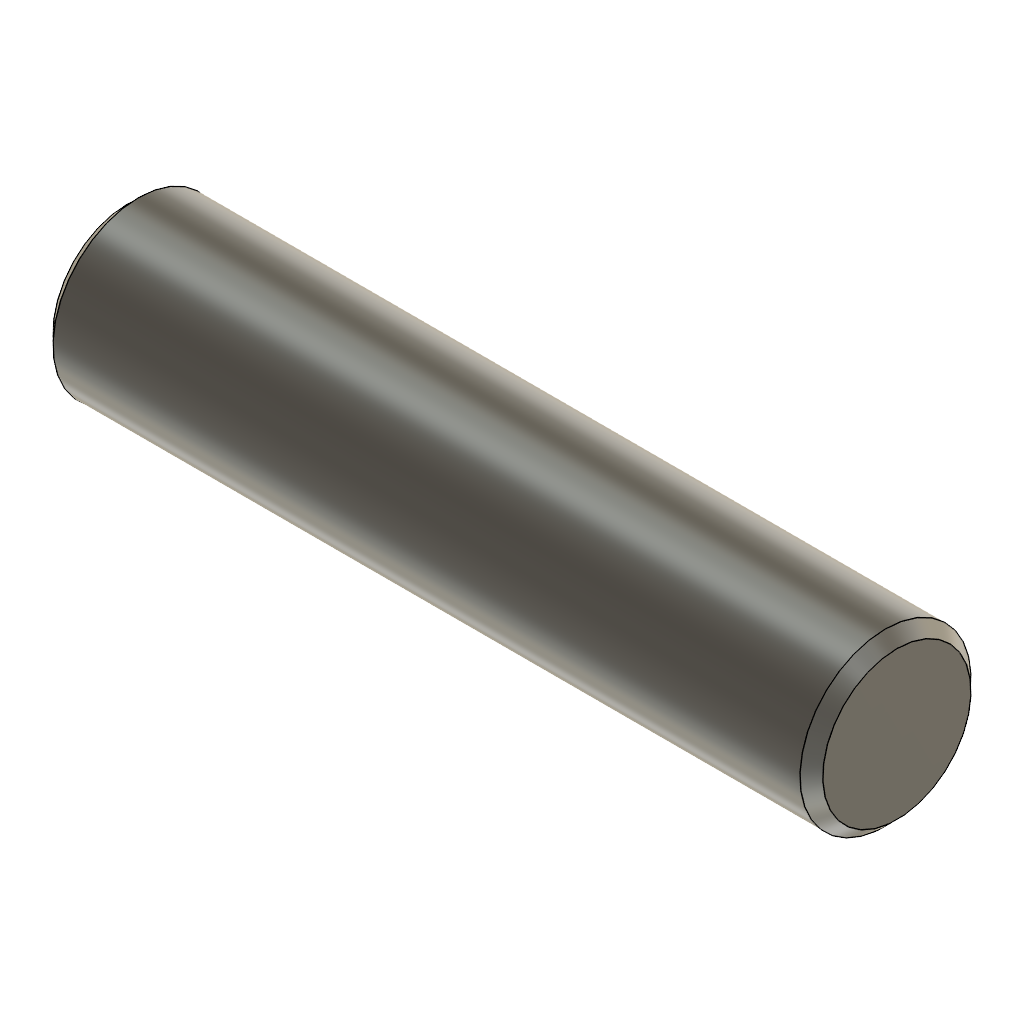
source (Autodesk Fusion 360 archive; units mm, degrees)
design "11_piston_pin"
Autodesk Fusion 360 part; units mm, degrees
sketch "Sketch1" plane through (0, 0, 0) normal (0, 1, 0) x (1, 0, 0)
  line L0 (-6.75, 0) -> (6.75, 0)
  line L1 (6.75, 0) -> (6.75, -1.3)
  line L2 (6.55, -1.5) -> (-6.55, -1.5)
  line L3 (-6.75, 0) -> (-6.75, -1.3)
  line L4 (6.75, -1.3) -> (6.55, -1.5)
  line L5 (-6.55, -1.5) -> (-6.75, -1.3)
  point P0 (6.75, -1.5)
  point P1 (-6.75, -1.5)
  dimension "d1" = 13.5
  dimension "d2" = 1.5
  dimension "d3" = 0.2
  dimension "d4" = 0.2
  dimension "d5" = 0.2
  dimension "d6" = 0.2
  constraint midpoint L0 origin
  constraint horizontal L0
  constraint vertical L1
  constraint perpendicular L1 L2
  constraint perpendicular L2 L3
  constraint coincident P0 L1
  constraint coincident P0 L2
  constraint coincident P1 L2
  constraint coincident P1 L3
  measures "d1" distance of L0.start L0.end
  measures "d2" distance of L0.end P0
  measures "d3" distance of P0 L1.end
  measures "d4" distance of P0 L2.start
  measures "d5" distance of P1 L2.end
  measures "d6" distance of P1 L3.end
revolve "Revolve1" add sketch "Sketch1" angle 360 about axis through (-6.75, 0, 0) along (1, 0, 0)
equation "d4 = d3"
equation "d6 = d5"

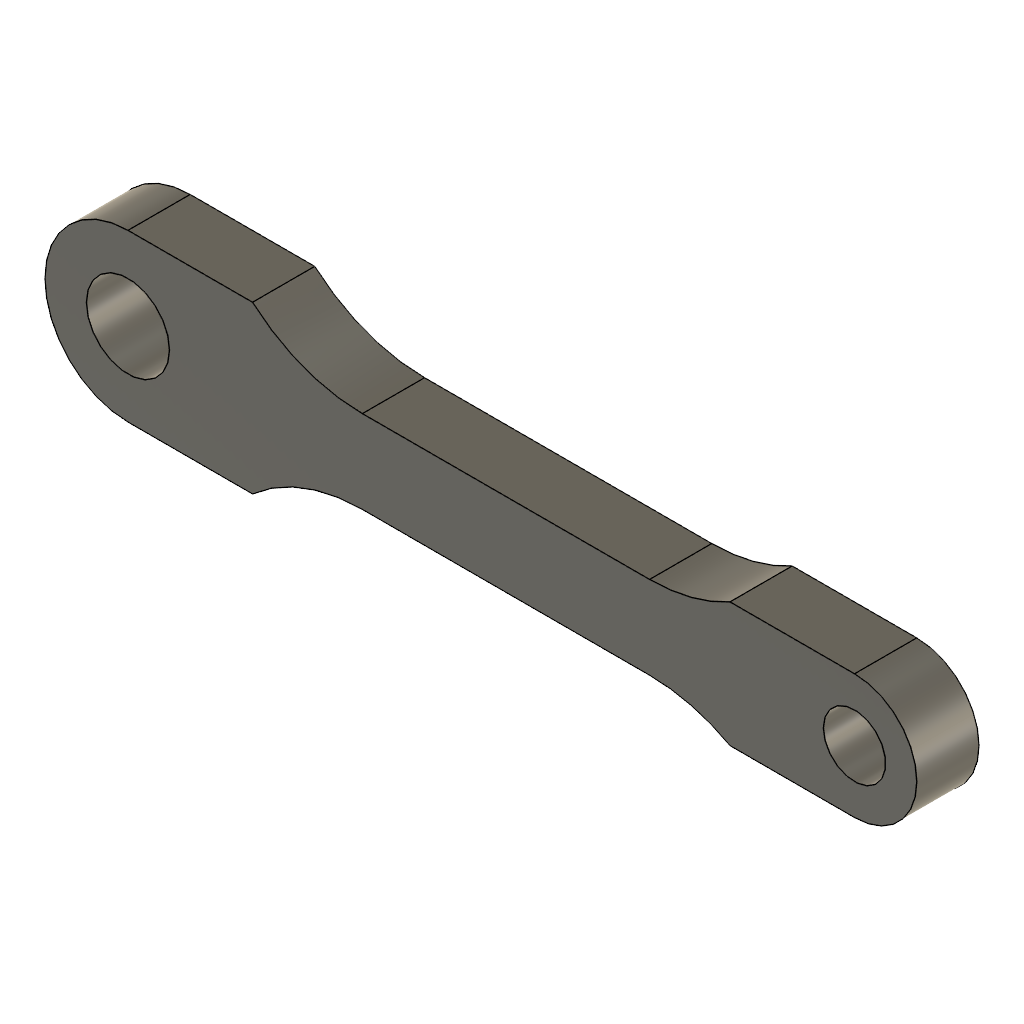
design "08_connecting_rod"
Autodesk Fusion 360 part; units mm, degrees
sketch "Sketch1" plane through (0, 0, 0) normal (0, 1, 0) x (1, 0, 0)
  line L0 (-17.5, 0) -> (17.5, 0) construction
  circle A0 centre (-17.5, 0) radius 2
  circle A1 centre (17.5, 0) radius 1.5
  arc A2 (-17.5, 4) -> (-17.5, -4) centre (-17.5, 0) ccw
  arc A3 (17.5, -3) -> (17.5, 3) centre (17.5, 0) ccw
  line L1 (17.5, 3) -> (11.5, 3)
  arc A4 (7.627, 2) -> (11.5, 3) centre (7.627, 10) ccw
  line L2 (7.627, 2) -> (-6.2085, 2)
  arc A5 (-11.5, 4) -> (-6.2085, 2) centre (-6.2085, 10) ccw
  line L3 (-17.5, 4) -> (-11.5, 4)
  arc A6 (-17.5, 4) -> (-17.5, -4) centre (-17.5, 0) ccw
  line L4 (7.627, -2) -> (-6.2085, -2)
  arc A7 (11.5, -3) -> (7.627, -2) centre (7.627, -10) ccw
  line L5 (17.5, -3) -> (11.5, -3)
  arc A8 (17.5, -3) -> (17.5, 3) centre (17.5, 0) ccw
  line L6 (-17.5, -4) -> (-11.5, -4)
  arc A9 (-6.2085, -2) -> (-11.5, -4) centre (-6.2085, -10) ccw
  dimension "d1" = 35
  dimension "d2" = 4
  dimension "d3" = 3
  dimension "d4" = 4
  dimension "d5" = 3
  dimension "d6" = 6
  dimension "d7" = 6
  dimension "d8" = 8
  dimension "d9" = 2
  constraint midpoint L0 origin
  constraint horizontal L0
  constraint coincident L0.start A0.centre
  constraint coincident L0.end A1.centre
  constraint horizontal L1
  constraint horizontal L2
  constraint tangent L2 A5
  constraint tangent A2 L3
  constraint horizontal L3
  constraint equal A4 A5
  constraint tangent A4 L2
  constraint tangent A3 L1
  constraint vertical L0.start A2.end
  constraint vertical L0.end A3.start
  constraint symmetric L0 A2.start A2.end
  constraint symmetric L0 A2.end A2.start
  constraint symmetric L0 A2 A6
  constraint symmetric L0 A3.start A3.end
  constraint symmetric L0 A3.end A3.start
  constraint symmetric L0 A3 A8
  constraint symmetric L0 L1.end A7.start
  constraint symmetric L0 A4.start L4.start
  constraint symmetric L0 A4 A7
  constraint symmetric L0 L2.end L4.end
  constraint symmetric L0 A5 A9
  constraint symmetric L0 A5.start L6.end
  measures "d1" distance of L0.start L0.end
  measures "d2" diameter of A0
  measures "d3" diameter of A1
  measures "d4" radius of A2
  measures "d5" radius of A3
  measures "d6" distance of A3.end L1.end
  measures "d7" distance of A2.start A5.start
  measures "d8" radius of A5
  measures "d9" distance of L0 L2
extrude "Extrude1" add sketch "Sketch1" along normal mid plane 3

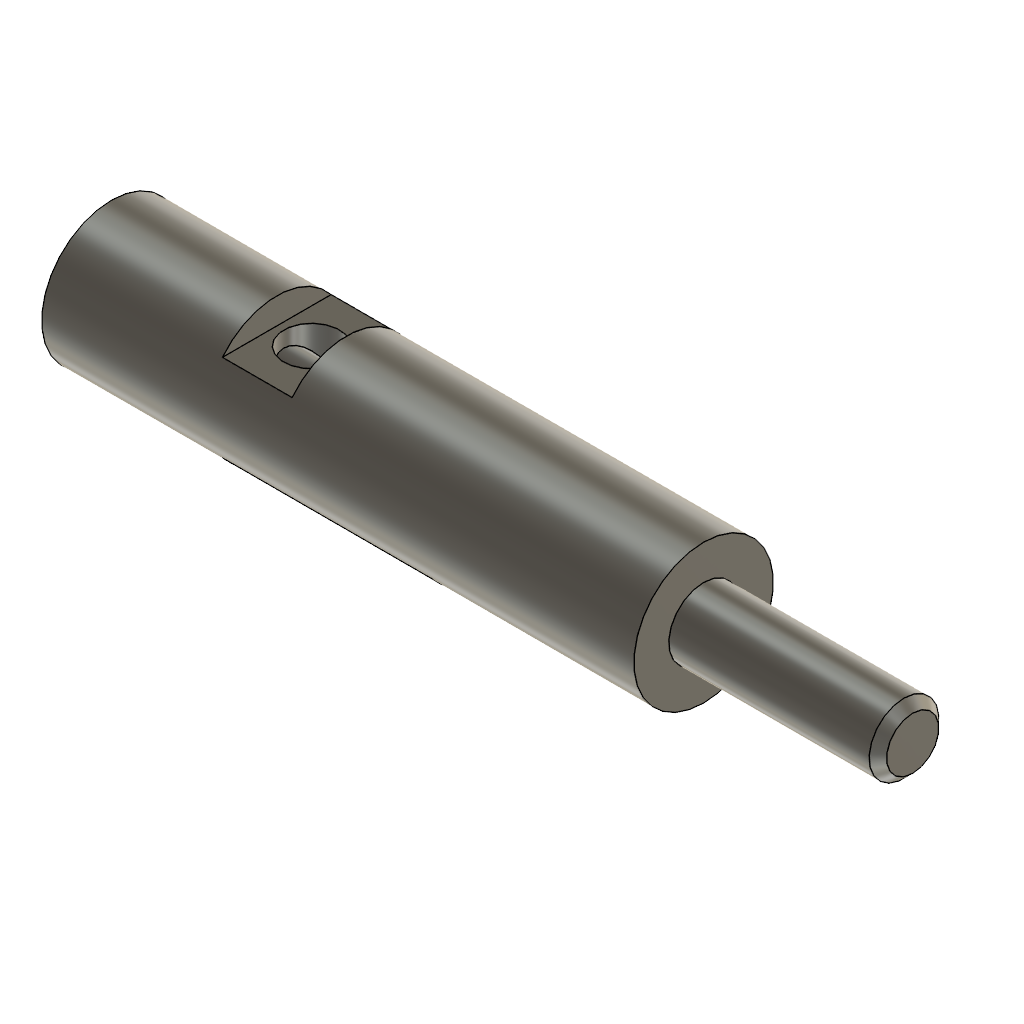
design "06_cranckshaft"
Autodesk Fusion 360 part; units mm, degrees
sketch "Sketch1" plane through (0, 0, 0) normal (0, 1, 0) x (1, 0, 0)
  line L0 (-23, 0) -> (23, 0)
  line L1 (-23, 0) -> (-23, -4)
  line L2 (-23, -4) -> (11, -4)
  line L3 (11, -4) -> (11, -2)
  line L4 (11, -2) -> (22.5, -2)
  line L5 (23, -1.5) -> (23, 0)
  line L6 (-23, 0) -> (-23, -1.6)
  line L7 (-23, -1.6) -> (-9, -1.6)
  line L8 (-9, -1.6) -> (-8.0762, 0)
  line L9 (22.5, -2) -> (23, -1.5)
  point P0 (23, -2)
  dimension "d1" = 46
  dimension "d2" = 4
  dimension "d3" = 34
  dimension "d4" = 1.6
  dimension "d5" = 14
  dimension "d6" = 120
  dimension "d7" = 2
  dimension "d30" = 0.5
  dimension "d31" = 0.5
  constraint midpoint L0 origin
  constraint horizontal L0
  constraint perpendicular L0 L1
  constraint perpendicular L1 L2
  constraint perpendicular L0 L3
  constraint perpendicular L1 L4
  constraint perpendicular L0 L5
  constraint perpendicular L0 L6
  constraint perpendicular L6 L7
  constraint coincident L0 L8.end
  constraint coincident P0 L4
  constraint coincident P0 L5
  measures "d1" distance of L0.start L0.end
  measures "d2" distance of L0.start L1.end
  measures "d3" distance of L1.end L2.end
  measures "d4" distance of L0.start L6.end
  measures "d5" distance of L6.end L7.end
  measures "d6" angle of L7 L8
  measures "d7" distance of L0.end P0
  measures "d30" distance of P0 L4.end
  measures "d31" distance of P0 L5.start
revolve "Revolve1" add sketch "Sketch1" angle 360 about axis through (-23, 0, 0) along (1, 0, 0) contours L0 L1 L2 L3 L4 L5 L7 L8 L9
sketch "Sketch4" plane through (0, 0, 0) normal (0, 1, 0) x (1, 0, 0)
  line L0 (-23, 4) -> (-23, -4)
  line L1 (-23, 4) -> (-13.5, 4)
  line L2 (-13.5, 4) -> (-1.5, 4)
  line L3 (-1.5, 4) -> (-1.5, 2.5)
  line L4 (-1.5, 2.5) -> (-13.5, 2.5)
  line L5 (-13.5, 2.5) -> (-13.5, 4)
  line L6 (-23, -4) -> (-11.5, -4)
  line L7 (-9.5, -2.5) -> (-13.5, -2.5)
  line L8 (-13.5, -2.5) -> (-13.5, -5.5)
  line L9 (-13.5, -5.5) -> (-9.5, -5.5)
  line L10 (-9.5, -5.5) -> (-9.5, -2.5)
  line L11 (-9.5, -2.5) -> (-13.5, -5.5) construction
  line L12 (-13.5, -2.5) -> (-9.5, -5.5) construction
  point P0 (-11.5, -4)
  dimension "d18" = 9.5
  dimension "d19" = 12
  dimension "d20" = 1.5
  dimension "d21" = 11.5
  dimension "d22" = 4
  dimension "d23" = 3
  constraint coincident L0.start L1.start
  constraint perpendicular L0 L1
  constraint horizontal L2
  constraint vertical L3
  constraint horizontal L4
  constraint vertical L5
  constraint coincident L0.end L6.start
  constraint perpendicular L0 L6
  constraint horizontal L7
  constraint perpendicular L7 L8
  constraint parallel L7 L9
  constraint parallel L8 L10
  constraint coincident L11 P0
  constraint coincident L12 P0
  constraint coincident P0 L6.end
  measures "d18" distance of L0.start L1.end
  measures "d19" distance of L1.end L2.end
  measures "d20" distance of L1.end L4.end
  measures "d21" distance of L0.end P0
  measures "d22" distance of L8.end L9.end
  measures "d23" distance of L7.end L8.end
extrude "Extrude3" cut sketch "Sketch4" along normal mid plane 22
sketch "Sketch5" plane through (0, 0, 0) normal (0, 0, 1) x (-1, 0, 0)
  line L0 (9.5, -3.1225) -> (13.5, -3.1225)
  line L1 (13.5, -3.1225) -> (13.5, 3.1225)
  line L2 (13.5, 3.1225) -> (9.5, 3.1225)
  line L3 (9.5, 3.1225) -> (9.5, -3.1225)
  circle A0 centre (11.5, 0) radius 1.6
  point P0 (23, 0)
  dimension "d26" = 3.2
  dimension "d27" = 11.5
  measures "d26" diameter of A0
  measures "d27" distance of A0.centre P0
extrude "Extrude4" cut sketch "Sketch5" along normal blind 8 contours A0
equation "d4 = ( 3.2 / 2 ) * 1 mm"
equation "d31 = d30"

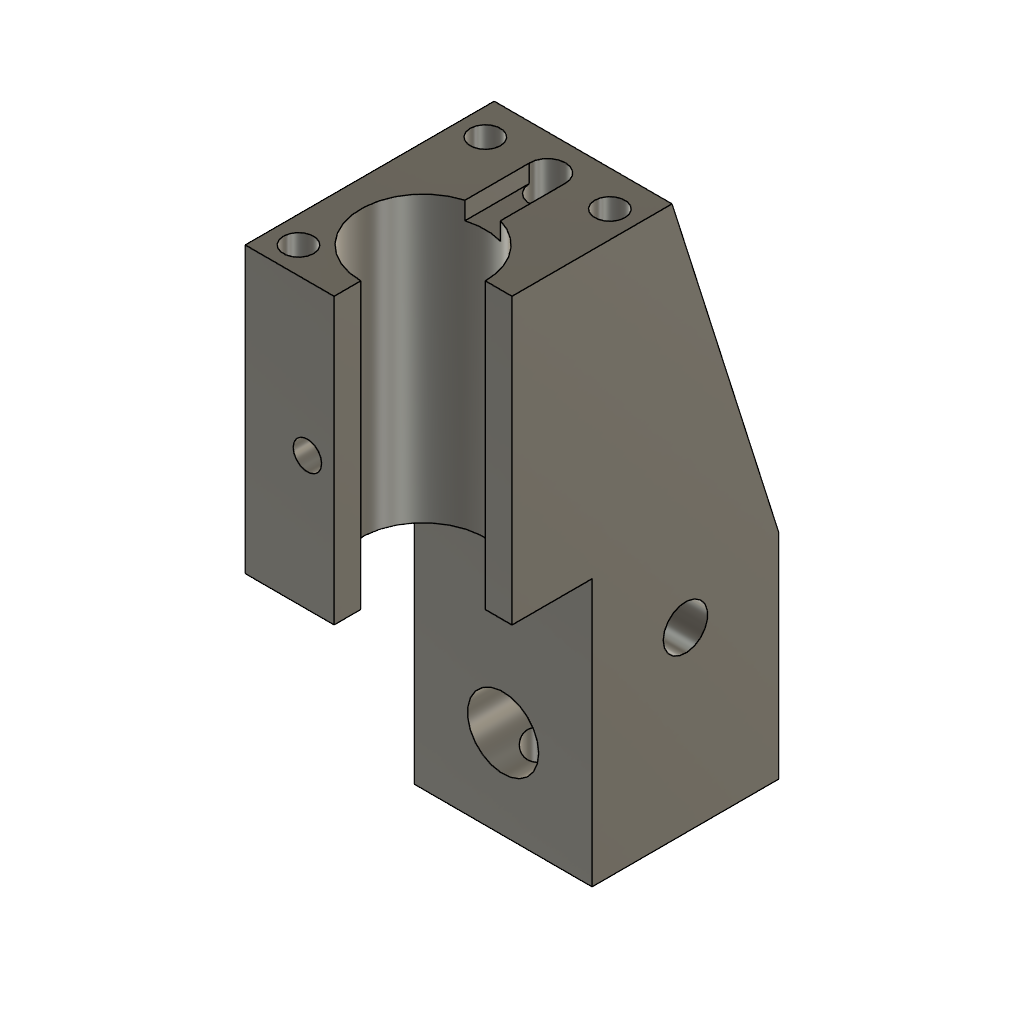
design "03_Engine_Block"
Autodesk Fusion 360 part; units mm, degrees
sketch "Sketch1" plane through (0, 0, 0) normal (1, 0, 0) x (0, 1, 0)
  line L0 (-10, 0) -> (18, 0)
  line L1 (18, 0) -> (30, -38)
  line L2 (30, -38) -> (30, -62)
  line L3 (30, -62) -> (9, -62)
  line L4 (9, -62) -> (9, -32)
  line L5 (9, -32) -> (-10, -32)
  line L6 (-10, -32) -> (-10, 0)
  circle A0 centre (19.5, -42) radius 2.5
  point P0 (19.5, -62)
  dimension "d1" = 28
  dimension "d2" = 12
  dimension "d3" = 38
  dimension "d4" = 21
  dimension "d5" = 30
  dimension "d7" = 10
  dimension "d8" = 62
  dimension "d23" = 5
  dimension "d24" = 20
  constraint horizontal L0
  constraint vertical L2
  constraint perpendicular L2 L3
  constraint perpendicular L3 L4
  constraint perpendicular L4 L5
  constraint coincident L0.start L6.end
  constraint perpendicular L5 L6
  constraint coincident origin L0
  constraint midpoint L3 P0
  constraint vertical A0.centre P0
  measures "d1" distance of L0.start L0.end
  measures "d2" horizontal distance of L0.end L1.end
  measures "d3" vertical distance of L0.end L1.end
  measures "d4" distance of L2.end L3.end
  measures "d5" vertical distance of L3.end L5.end
  measures "d7" horizontal distance of origin L0.start
  measures "d8" vertical distance of L3.end L0.start
  measures "d23" diameter of A0
  measures "d24" distance of L3 A0.centre
extrude "Extrude1" add sketch "Sketch1" along normal mid plane 20
sketch "Sketch2" plane through (0, 0, 0) normal (0, 0, 1) x (-1, 0, 0)
  line L0 (10, 10) -> (-10, 10)
  line L1 (-10, 10) -> (-10, -18)
  line L2 (-10, -18) -> (10, -18)
  line L3 (10, -18) -> (10, 10)
  circle A0 centre (0, 0) radius 7
  dimension "d11" = 14
  constraint coincident A0.centre origin
  measures "d11" diameter of A0
extrude "Extrude2" cut sketch "Sketch2" against normal blind 40 contours A0
sketch "Sketch4" plane through (0, 30, 0) normal (0, 1, 0) x (-1, 0, 0)
  line L0 (10, -38) -> (-10, -38)
  line L1 (-10, -38) -> (-10, -62)
  line L2 (-10, -62) -> (10, -62)
  line L3 (10, -62) -> (10, -38)
  circle A0 centre (0, -52) radius 4
  dimension "d20" = 8
  dimension "d21" = 10
  constraint vertical origin A0.centre
  measures "d20" diameter of A0
  measures "d21" distance of L2 A0.centre
extrude "Extrude3" cut sketch "Sketch4" against normal through all contours A0
sketch "Sketch3" plane through (0, 0, 0) normal (1, 0, 0) x (0, 1, 0)
  line L0 (18, 0) -> (-10, 0)
  line L1 (14, 0) -> (14, -49.9021)
  line L2 (14, 0) -> (12, 0)
  line L3 (12, 0) -> (12, -30)
  line L4 (12, -30) -> (12.75, -30)
  line L5 (12.75, -30) -> (12.75, -49.9021)
  line L6 (12.75, -49.9021) -> (14, -49.9021)
  dimension "d14" = 2
  dimension "d15" = 30
  dimension "d17" = 24
  dimension "d18" = 1.25
  constraint coincident L0 L1.start
  constraint perpendicular L0 L1
  constraint perpendicular L1 L2
  constraint perpendicular L0 L3
  constraint perpendicular L3 L4
  constraint vertical L5
  constraint horizontal L6
  measures "d14" distance of L1.start L2.end
  measures "d15" distance of L2.end L3.end
  measures "d17" distance of L0.end L1.start
  measures "d18" distance of L1 L5
revolve "Revolve1" cut sketch "Sketch3" angle 360 about axis through (0, 14, 0) along (0, 0, -1)
sketch "Sketch6" plane through (0, -10, 0) normal (0, -1, 0) x (1, 0, 0)
  line L0 (-10, -32) -> (10, -32)
  line L1 (10, -32) -> (10, 0)
  line L2 (10, 0) -> (-10, 0)
  line L3 (-10, 0) -> (-10, -32)
  circle A0 centre (-3, -17) radius 1.6
  circle A1 centre (3, -17) radius 1.6
  point P0 (-3, -17)
  point P1 (3, -17)
  dimension "d25" = 17
  dimension "d26" = 6
  dimension "d27" = 3
  dimension "d28" = 3.2
  constraint horizontal P0 P1
  constraint coincident P0 A0.centre
  constraint coincident P1 A1.centre
  constraint equal A0 A1
  measures "d25" vertical distance of L1.end P1
  measures "d26" distance of P0 P1
  measures "d27" horizontal distance of origin P1
  measures "d28" diameter of A0
extrude "Extrude4" cut sketch "Sketch6" against normal blind 9 contours A0 | A1
sketch "Sketch7" plane through (0, 0, 0) normal (0, 0, 1) x (-1, 0, 0)
  circle A0 centre (0, -14) radius 2
  circle A1 centre (0, 0) radius 7
  line L0 (10, 10) -> (-10, 10)
  line L1 (-10, 10) -> (-10, -18)
  line L2 (-10, -18) -> (10, -18)
  line L3 (10, -18) -> (10, 10)
  line L4 (1.9986, -14.0753) -> (-1.9986, -14.0753)
  line L5 (-1.9986, -14.0753) -> (-1.9986, -6.7086)
  line L6 (-1.9986, -6.7086) -> (1.9986, -6.7086)
  line L7 (1.9986, -6.7086) -> (1.9986, -14.0753)
  line L8 (-1.9986, -14.0753) -> (1.9986, -14.0753)
  constraint horizontal L4
  constraint vertical L5
  constraint horizontal L6
  constraint vertical L7
  constraint coincident A1 L5.end
  constraint coincident A0 L4.start
  constraint coincident A0 L4.end
  constraint perpendicular L7 L8
extrude "Extrude5" cut sketch "Sketch7" against normal blind 2 contours A0 L4 L5 L7 L8 | A0 A1 L5 L7 | A1 L6 picked at (-0.3366, -6.7813)
sketch "Sketch8" plane through (0, 0, 0) normal (0, 0, 1) x (-1, 0, 0)
  line L0 (10, 10) -> (-10, 10)
  line L1 (-10, 10) -> (-10, -18)
  line L2 (-10, -18) -> (10, -18)
  line L3 (10, -18) -> (10, 10)
  line L4 (1.9986, -6.7086) -> (1.9986, -13.9247)
  arc A0 (-1.9986, -13.9247) -> (1.9986, -13.9247) centre (0, -14) ccw
  line L5 (-1.9986, -13.9247) -> (-1.9986, -6.7086)
  arc A1 (1.9986, -6.7086) -> (-1.9986, -6.7086) centre (0, 0) ccw
  point P0 (7, 7)
  point P1 (7, -14)
  point P2 (-7, -14)
  point P3 (-7, 7)
  point P4 (7, 7)
  dimension "d33" = 3
  dimension "d34" = 7
  dimension "d35" = 14
  dimension "d36" = 24
  constraint coincident P4 P0
  constraint horizontal P1 P2
  constraint vertical P2 P3
  constraint horizontal P3 P4
  constraint vertical P4 P1
  measures "d33" distance of L0 P4
  measures "d34" horizontal distance of A1.centre P4
  measures "d35" horizontal distance of P4 P3
  measures "d36" distance of L0 P1
hole "Hole1" at (-7, 14, 0) at (-7, -7, 0) at (7, -7, 0) at (7, 14, 0) direction (0, 0, -1) diameter 3.4 depth 9 tip angle 118
sketch "Sketch9" plane through (0, 0, -62) normal (0, 0, -1) x (1, 0, 0)
  line L0 (-10, -30) -> (10, -30)
  line L1 (10, -30) -> (10, -9)
  line L2 (10, -9) -> (-10, -9)
  line L3 (-10, -9) -> (-10, -30)
  point P0 (0, -22)
  point P1 (0, -14)
  point P2 (0, -30)
  dimension "d40" = 8
  dimension "d41" = 8
  constraint midpoint L0 P2
  constraint vertical P0 P2
  constraint vertical P0 P1
  measures "d40" distance of P0 P2
  measures "d41" distance of P0 P1
hole "Hole2" at (0, 22, -62) at (0, 14, -62) direction (0, 0, 1) diameter 4.5 depth 9 tip angle 118
sketch "Çizim10" plane through (0, 0, 0) normal (0, 0, 1) x (-1, 0, 0)
  line L0 (1.9986, -6.7086) -> (1.9986, -13.9247)
  arc A0 (-1.9986, -13.9247) -> (1.9986, -13.9247) centre (0, -14) ccw
  line L1 (-1.9986, -13.9247) -> (-1.9986, -6.7086)
  arc A1 (1.9986, -6.7086) -> (-1.9986, -6.7086) centre (0, 0) ccw
  line L2 (10, 10) -> (-10, 10)
  line L3 (-10, 10) -> (-10, -18)
  line L4 (-10, -18) -> (10, -18)
  line L5 (10, -18) -> (10, 10)
  circle A2 centre (-7, -14) radius 1.7
  circle A3 centre (7, 7) radius 1.7
  circle A4 centre (7, -14) radius 1.7
  circle A5 centre (-7, 7) radius 1.7
  line L6 (0, 0) -> (-10, 0)
  line L7 (-10, 0) -> (-10, 10)
  line L8 (-10, 10) -> (0, 10)
  line L9 (0, 10) -> (0, 0)
  constraint horizontal L6
  constraint vertical L7
  constraint horizontal L8
  constraint vertical L9
  constraint coincident L2.end L3.start
  constraint coincident A1.centre L6.start
extrude "Ekstrüzyon6" cut sketch "Çizim10" against normal blind 35 contours A1 L6 L9 | A1 L2 L3 L6 L7 L8 L9 | A5
equation "d18 = ( 2.5 / 2 ) * 1 mm"

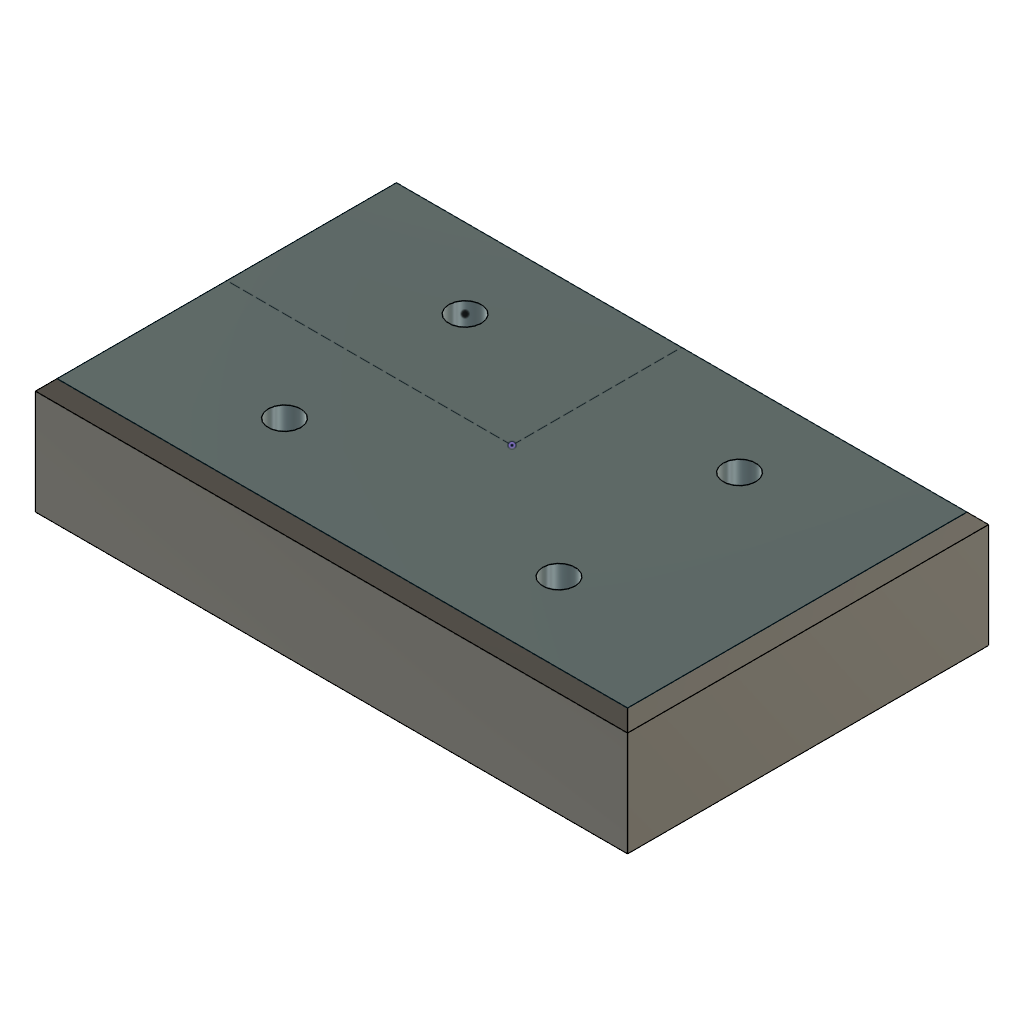
design "01_base_plate"
Autodesk Fusion 360 part; units mm, degrees
sketch "Sketch1" plane through (0, 0, 0) normal (0, 0, 1) x (1, 0, 0)
  line L0 (41, -25) -> (-41, -25)
  line L1 (-41, -25) -> (-41, 25)
  line L2 (-41, 25) -> (41, 25)
  line L3 (41, 25) -> (41, -25)
  line L4 (41, -25) -> (-41, 25) construction
  line L5 (-41, -25) -> (41, 25) construction
  dimension "d1" = 82
  dimension "d2" = 50
  constraint horizontal L0
  constraint perpendicular L0 L1
  constraint parallel L0 L2
  constraint parallel L1 L3
  constraint coincident L4 origin
  constraint coincident L5 origin
  measures "d1" distance of L1.end L2.end
  measures "d2" distance of L0.end L1.end
extrude "Extrude1" add sketch "Sketch1" along normal blind 16
chamfer "Chamfer1" distance 1.5 angle 45 1 faces at (-13.6667, -8.3333, 16) tangent chain off
sketch "Sketch2" plane through (0, 0, 16) normal (0, 0, 1) x (-1, 0, 0)
  line L0 (39.5, 23.5) -> (-39.5, 23.5)
  line L1 (-39.5, 23.5) -> (-39.5, -23.5)
  line L2 (-39.5, -23.5) -> (39.5, -23.5)
  line L3 (39.5, -23.5) -> (39.5, 23.5)
  line L4 (0, 0) -> (0, -23.5) construction
  line L5 (0, 0) -> (39.5, 0) construction
  point P0 (19, -12.5)
  dimension "d6" = 19
  dimension "d7" = 12.5
  constraint coincident L4.start L5.start
  constraint midpoint L2 L4.end
  constraint midpoint L3 L5.end
  measures "d6" horizontal distance of L4.start P0
  measures "d7" vertical distance of L4.start P0
hole "Hole1" at (-19, 12.5, 16) direction (0, 0, -1) diameter 4.5 depth 8 tip angle 118
mirror "Mirror1" about plane through (0, 0, 0) normal (1, 0, 0) of "Hole1"
mirror "Mirror2" about plane through (0, 0, 0) normal (0, 1, 0) of "Hole1", "Mirror1"
equation "d6 = ( 38 / 2 ) * 1 mm"
equation "d7 = ( 25 / 2 ) * 1 mm"

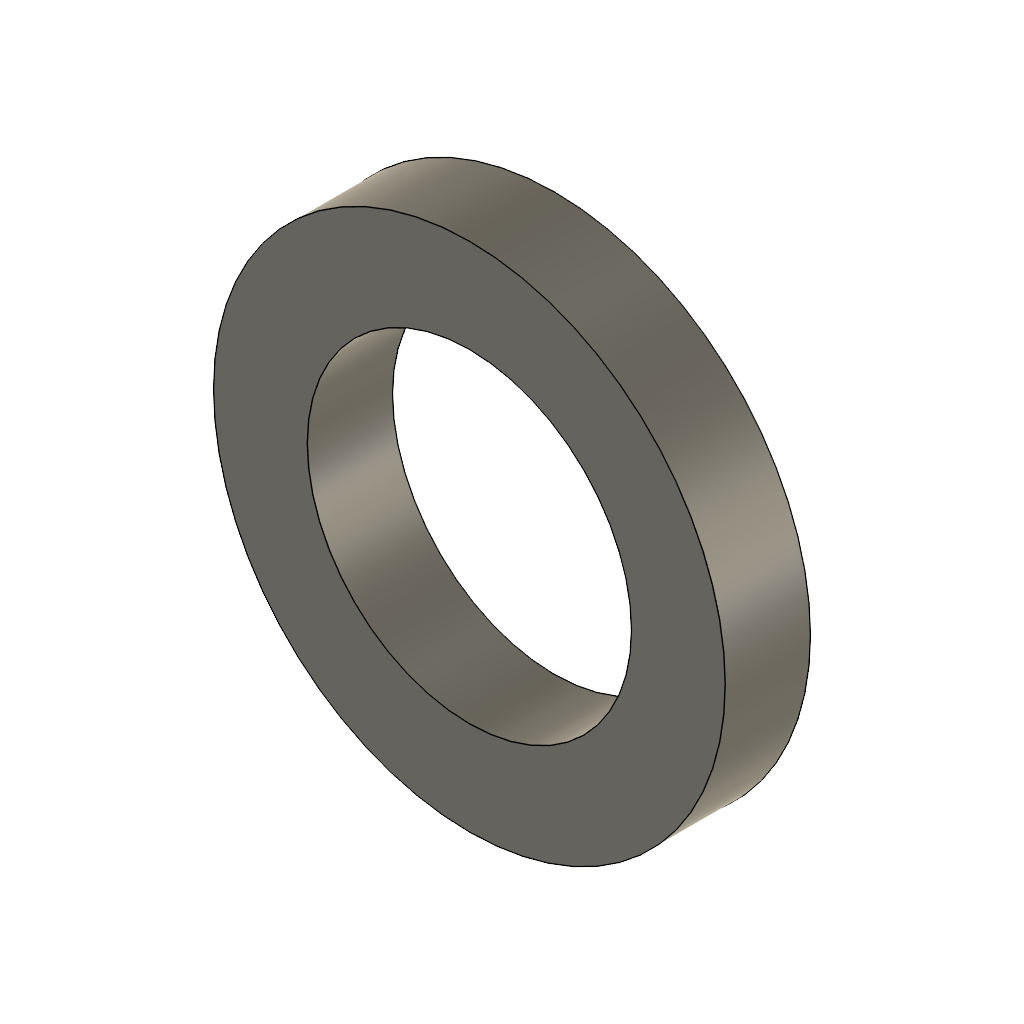
design "12_washer"
Autodesk Fusion 360 part; units mm, degrees
sketch "Sketch1" plane through (0, 0, 0) normal (0, 1, 0) x (1, 0, 0)
  circle A0 centre (0, 0) radius 1.9
  circle A1 centre (0, 0) radius 3
  dimension "d1" = 3.8
  dimension "d2" = 6
  constraint coincident A0.centre A1.centre
  constraint concentric A0 A1
  measures "d1" diameter of A0
  measures "d2" diameter of A1
extrude "Extrude1" add sketch "Sketch1" along normal mid plane 1

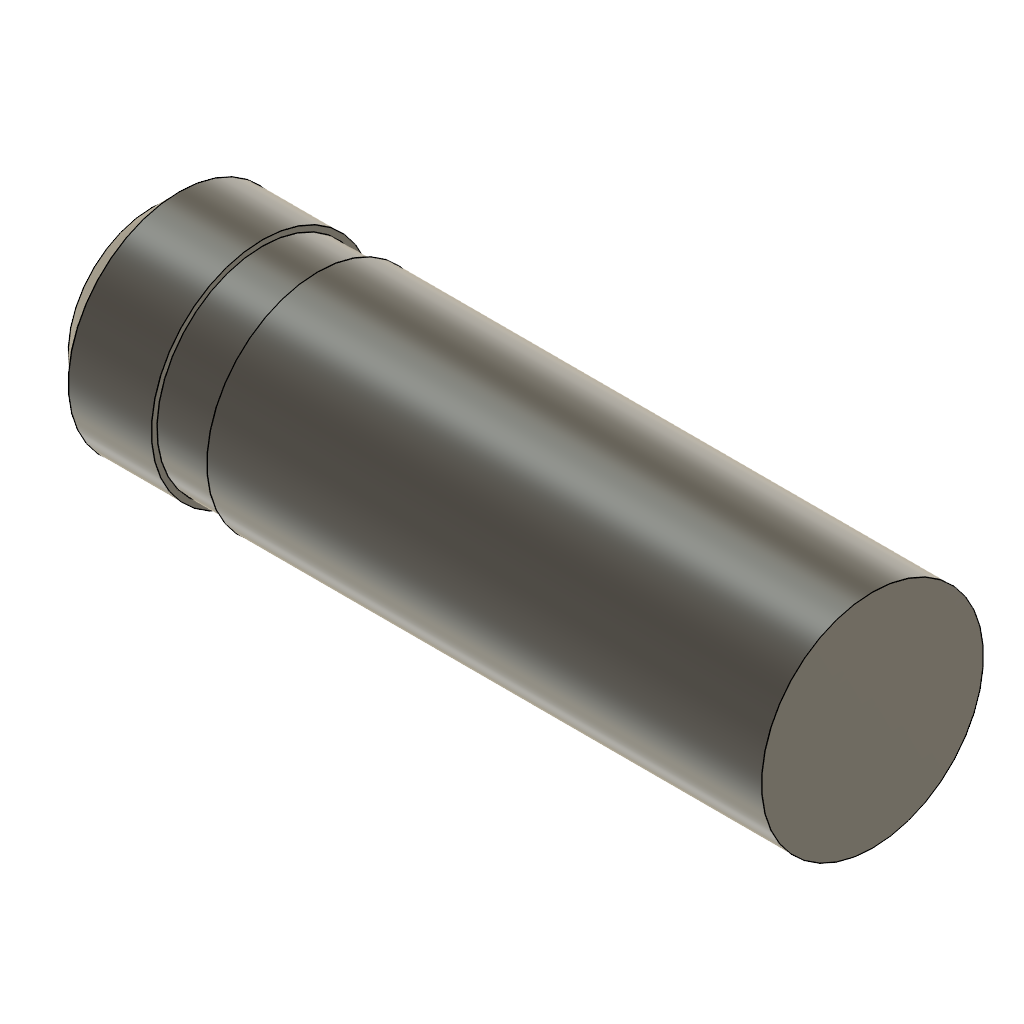
design "10_crank_pin"
Autodesk Fusion 360 part; units mm, degrees
sketch "Sketch1" plane through (0, 0, 0) normal (0, 1, 0) x (1, 0, 0)
  line L0 (-6.5, 0) -> (6.5, 0)
  line L1 (6.5, 0) -> (6.5, -2)
  line L2 (6.5, -2) -> (-3.5, -2)
  line L3 (-3.5, -2) -> (-3.5, -1.9)
  line L4 (-3.5, -1.9) -> (-4.5, -1.9)
  line L5 (-4.5, -1.9) -> (-4.5, -2)
  line L6 (-4.5, -2) -> (-6, -2)
  line L7 (-6.5, -1.5) -> (-6.5, 0)
  line L8 (-6, -2) -> (-6.5, -1.5)
  point P0 (-6.5, -2)
  dimension "d1" = 13
  dimension "d2" = 2
  dimension "d3" = 10
  dimension "d4" = 1
  dimension "d5" = 1.9
  dimension "d6" = 0.5
  dimension "d7" = 0.5
  constraint midpoint L0 origin
  constraint horizontal L0
  constraint perpendicular L0 L1
  constraint perpendicular L1 L2
  constraint perpendicular L2 L3
  constraint perpendicular L3 L4
  constraint perpendicular L4 L5
  constraint perpendicular L5 L6
  constraint perpendicular L0 L7
  constraint coincident P0 L6
  constraint coincident P0 L7
  constraint collinear L2 L6
  measures "d1" distance of L0.start L0.end
  measures "d2" distance of L0.end L1.end
  measures "d3" distance of L1.end L2.end
  measures "d4" distance of L3.end L4.end
  measures "d5" distance of L0 L4
  measures "d6" distance of P0 L6.end
  measures "d7" distance of P0 L7.start
revolve "Revolve1" add sketch "Sketch1" angle 360 about axis through (-6.5, 0, 0) along (1, 0, 0)
equation "d5 = ( 3.8 / 2 ) * 1 mm"
equation "d7 = d6"

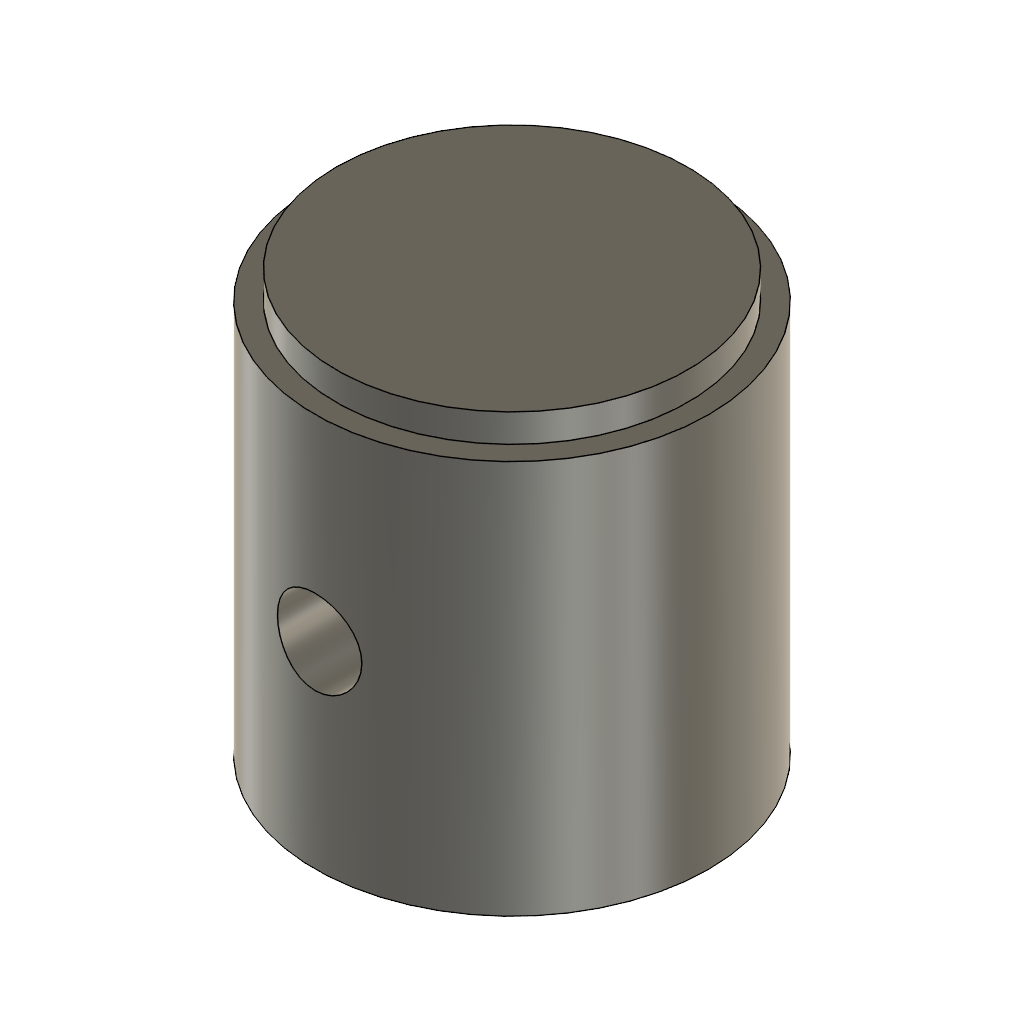
design "09_piston"
Autodesk Fusion 360 part; units mm, degrees
sketch "Sketch1" plane through (0, 0, 0) normal (0, 1, 0) x (1, 0, 0)
  line L0 (0, 0) -> (0, -30.1355) construction
  line L1 (0, 0) -> (-6.2, 0) construction
  line L2 (-6.2, 0) -> (-7, 0)
  line L3 (-7, 0) -> (-7, -14)
  line L4 (-7, -14) -> (-6.25, -14)
  line L5 (-6.25, -14) -> (-6.25, -15)
  line L6 (-6.25, -15) -> (0, -15)
  line L7 (0, -15) -> (0, -13.8541)
  line L8 (0, -13.8541) -> (-4.75, -11)
  line L9 (-4.75, -11) -> (-4.75, -3.9838)
  line L10 (-4.75, -3.9838) -> (-6.2, 0)
  dimension "d1" = 6.2
  dimension "d4" = 1
  dimension "d5" = 4.75
  dimension "d6" = 70
  dimension "d7" = 59
  dimension "d8" = 11
  dimension "d9" = 6.25
  dimension "d10" = 7
  dimension "d16" = 15
  constraint coincident L0.start L1.start
  constraint vertical L0
  constraint perpendicular L0 L1
  constraint parallel L1 L2
  constraint perpendicular L1 L3
  constraint perpendicular L3 L4
  constraint perpendicular L4 L5
  constraint coincident L0 L6.end
  constraint perpendicular L0 L6
  constraint coincident L0 L7.end
  constraint parallel L0 L9
  measures "d1" distance of L0.start L1.end
  measures "d4" distance of L4.end L5.end
  measures "d5" distance of L0 L9
  measures "d6" angle of L1 L10
  measures "d7" angle of L0 L8
  measures "d8" distance of L1 L8.end
  measures "d9" distance of L5.end L6.end
  measures "d10" distance of L0 L3
  measures "d16" distance of L1 L6
revolve "Revolve1" add sketch "Sketch1" angle 360 about axis through (0, 0, 0) along (0, 0, 1)
sketch "Sketch2" plane through (0, 0, 0) normal (0, 1, 0) x (1, 0, 0)
  circle A0 centre (0, -7) radius 1.5
  dimension "d12" = 3
  dimension "d13" = 7
  constraint vertical origin A0.centre
  measures "d12" diameter of A0
  measures "d13" distance of origin A0.centre
extrude "Extrude1" cut sketch "Sketch2" along normal mid plane 38

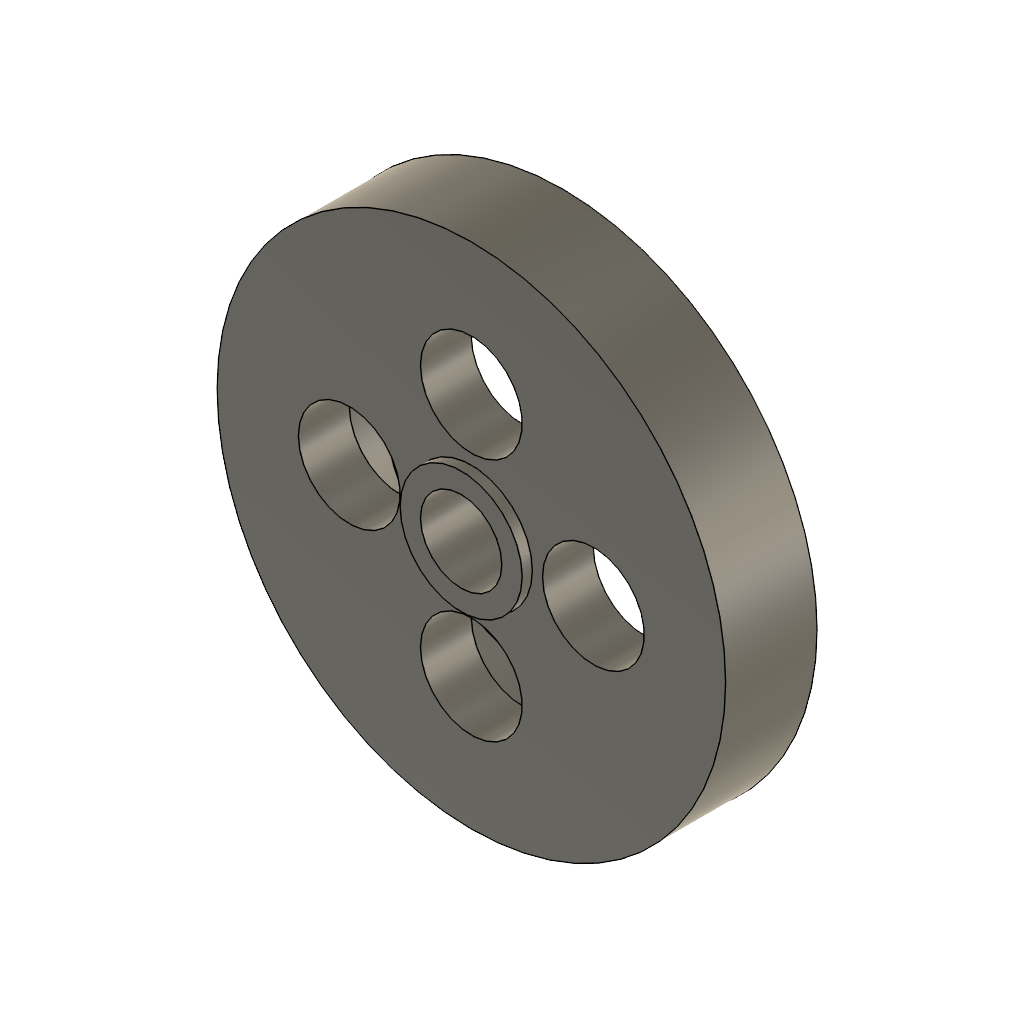
design "5_Fly_wheel"
Autodesk Fusion 360 part; units mm, degrees
sketch "Sketch1" plane through (0, 0, 0) normal (1, 0, 0) x (0, 1, 0)
  line L0 (0, 0) -> (5, 0)
  line L1 (5, 0) -> (5, 18)
  line L2 (5, 18) -> (9, 18)
  line L3 (9, 18) -> (9, 25)
  line L4 (9, 25) -> (0, 25)
  line L5 (0, 25) -> (0, 0)
  dimension "d1" = 5
  dimension "d2" = 18
  dimension "d3" = 4
  dimension "d4" = 9
  dimension "d5" = 25
  constraint coincident L0.start L5.end
  constraint horizontal L0
  constraint perpendicular L0 L1
  constraint perpendicular L1 L2
  constraint perpendicular L2 L3
  constraint perpendicular L3 L4
  measures "d1" distance of L0.start L0.end
  measures "d2" distance of L0.end L1.end
  measures "d3" distance of L1.end L2.end
  measures "d4" distance of L3.end L4.end
  measures "d5" distance of L0.start L4.end
revolve "Revolve1" add sketch "Sketch1" angle 360 about axis through (0, 0, 0) along (0, 1, 0)
sketch "Sketch2" plane through (0, 0, 0) normal (0, -1, 0) x (1, 0, 0)
  circle A0 centre (0, 0) radius 25
  circle A1 centre (0, 0) radius 12 construction
  circle A2 centre (0, 12) radius 5
  circle A3 centre (0, 0) radius 4
  circle A4 centre (-12, 0) radius 5
  circle A5 centre (0, -12) radius 5
  circle A6 centre (12, 0) radius 5
  point P0 (0, 12)
  dimension "d7" = 24
  dimension "d8" = 10
  dimension "d9" = 8
  dimension "d11" = 360
  constraint coincident A0.centre A1.centre
  constraint coincident A1 P0
  constraint vertical A0.centre A2.centre
  constraint coincident P0 A2.centre
  constraint concentric A1 A3
  measures "d7" diameter of A1
  measures "d8" diameter of A2
  measures "d9" diameter of A3
extrude "Extrude1" cut sketch "Sketch2" against normal through all contours A2 | A3 | A4 | A5 | A6
sketch "Sketch3" plane through (0, 0, 0) normal (0, -1, 0) x (1, 0, 0)
  circle A0 centre (0, 0) radius 25
  circle A1 centre (0, -12) radius 5
  circle A2 centre (0, 12) radius 5
  circle A3 centre (-12, 0) radius 5
  circle A4 centre (12, 0) radius 5
  circle A5 centre (0, 0) radius 4
  circle A6 centre (0, 0) radius 4
  circle A7 centre (0, 0) radius 6
  dimension "d13" = 12
  constraint concentric A6 A7
  measures "d13" diameter of A7
extrude "Extrude2" add sketch "Sketch3" along normal blind 1 contours A7
equation "d2 = ( 36 / 2 ) * 1 mm"

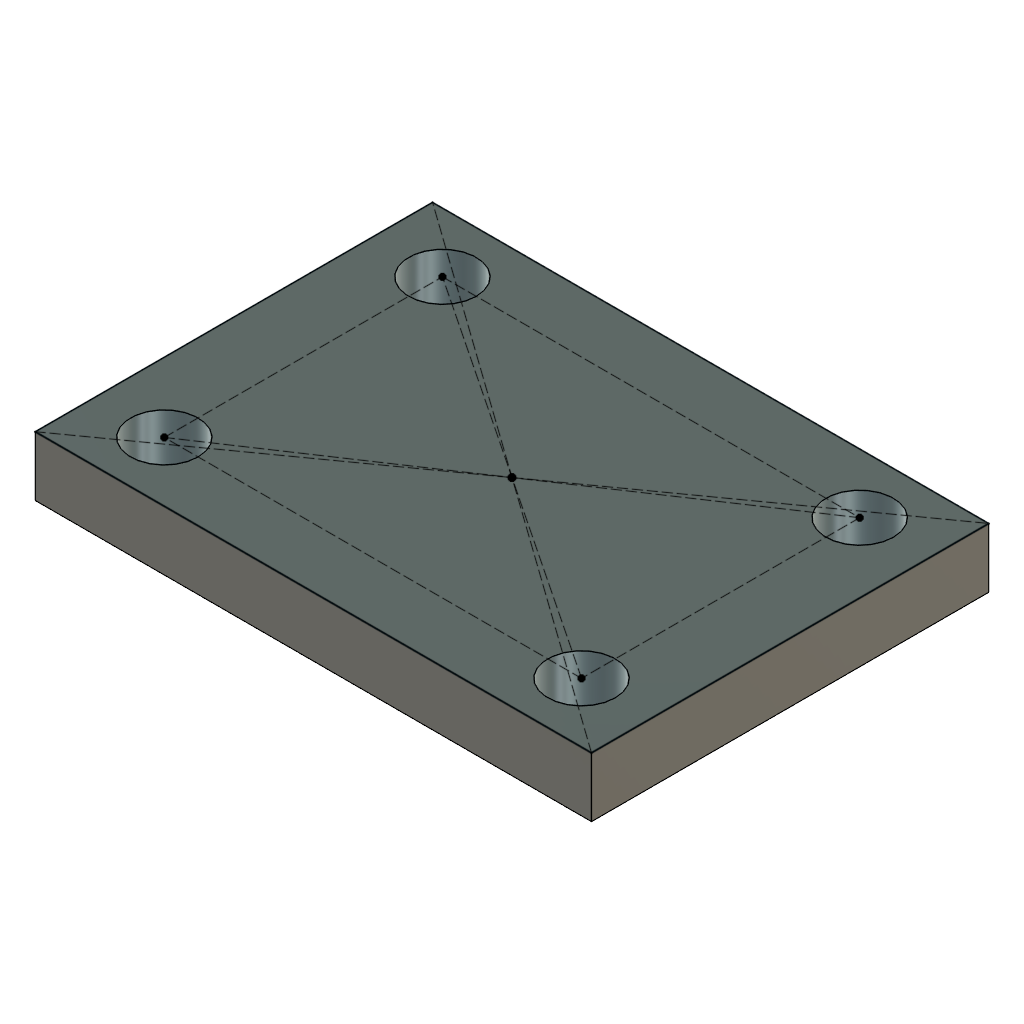
design "04_cylinder_head"
Autodesk Fusion 360 part; units mm, degrees
sketch "Sketch1" plane through (0, 0, 0) normal (0, 0, 1) x (1, 0, 0)
  line L0 (14, -10) -> (-14, -10)
  line L1 (-14, -10) -> (-14, 10)
  line L2 (-14, 10) -> (14, 10)
  line L3 (14, 10) -> (14, -10)
  line L4 (14, -10) -> (-14, 10) construction
  line L5 (-14, -10) -> (14, 10) construction
  line L6 (10.5, -7) -> (-10.5, -7) construction
  line L7 (-10.5, -7) -> (-10.5, 7) construction
  line L8 (-10.5, 7) -> (10.5, 7) construction
  line L9 (10.5, 7) -> (10.5, -7) construction
  line L10 (10.5, -7) -> (-10.5, 7) construction
  line L11 (-10.5, -7) -> (10.5, 7) construction
  point P0 (-10.5, 7)
  point P1 (10.5, 7)
  point P2 (10.5, -7)
  point P3 (-10.5, -7)
  dimension "d1" = 28
  dimension "d2" = 20
  dimension "d3" = 21
  dimension "d4" = 14
  constraint horizontal L0
  constraint perpendicular L0 L1
  constraint parallel L0 L2
  constraint parallel L1 L3
  constraint coincident L4 origin
  constraint coincident L5 origin
  constraint horizontal L6
  constraint perpendicular L6 L7
  constraint parallel L6 L8
  constraint parallel L7 L9
  constraint coincident L10 origin
  constraint coincident L11 origin
  constraint coincident P0 L7.end
  constraint coincident P1 L8.end
  constraint coincident P2 L6.start
  constraint coincident P3 L6.end
  measures "d1" distance of L1.end L2.end
  measures "d2" distance of L0.end L1.end
  measures "d3" distance of P0 P1
  measures "d4" distance of P3 P0
extrude "Extrude1" add sketch "Sketch1" against normal blind 3
hole "Hole1" at (10.5, 7, 0) at (-10.5, 7, 0) at (-10.5, -7, 0) at (10.5, -7, 0) direction (0, 0, -1) diameter 3.4 end through all
